p13_flangia (Autodesk Fusion 360 design; units mm, degrees)
Autodesk Fusion 360 part; units mm, degrees
sketch "Schizzo1" plane through (0, 0, 0) normal (0, 0, 1) x (1, 0, 0)
  line L0 (0, 0) -> (10000, 0)
  line L1 (10000, 0) -> (10000, 8000)
  line L2 (10000, 8000) -> (0, 8000)
  line L3 (0, 8000) -> (0, 0)
  line L4 (300, 300) -> (6000, 300)
  line L5 (6000, 300) -> (6000, 7700)
  line L6 (6000, 7700) -> (300, 7700)
  line L7 (300, 7700) -> (300, 300)
  line L8 (6100, 300) -> (9700, 300)
  line L9 (9700, 300) -> (9700, 4000)
  line L10 (9700, 4000) -> (6100, 4000)
  line L11 (6100, 4000) -> (6100, 300)
  line L12 (6100, 4100) -> (9700, 4100)
  line L13 (9700, 4100) -> (9700, 7700)
  line L14 (9700, 7700) -> (6100, 7700)
  line L15 (6100, 7700) -> (6100, 4100)
sketch "Schizzo2" plane through (0, 0, 0) normal (0, 0, 1) x (1, 0, 0)
  line L0 (2000, 0) -> (2900, 0)
  line L1 (2900, 0) -> (2900, 300)
  line L2 (2900, 300) -> (2000, 300)
  line L3 (2000, 300) -> (2000, 0)
  line L4 (6000, 1500) -> (6100, 1500)
  line L5 (6100, 1500) -> (6100, 2300)
  line L6 (6100, 2300) -> (6000, 2300)
  line L7 (6000, 2300) -> (6000, 1500)
  line L8 (6000, 5500) -> (6100, 5500)
  line L9 (6100, 5500) -> (6100, 6300)
  line L10 (6100, 6300) -> (6000, 6300)
  line L11 (6000, 6300) -> (6000, 5500)
sketch "Schizzo3" plane through (0, 0, 0) normal (0, 0, 1) x (1, 0, 0)
  line L0 (0, 3000) -> (300, 3000)
  line L1 (300, 3000) -> (300, 4500)
  line L2 (300, 4500) -> (0, 4500)
  line L3 (0, 4500) -> (0, 3000)
  line L4 (7400, 7700) -> (8600, 7700)
  line L5 (8600, 7700) -> (8600, 8000)
  line L6 (8600, 8000) -> (7400, 8000)
  line L7 (7400, 8000) -> (7400, 7700)
sketch "Schizzo4" plane through (0, 0, 0) normal (0, 0, 1) x (1, 0, 0)
  circle A0 centre (0, 0) radius 40
  circle A1 centre (0, 0) radius 15
extrude "Estrusione5" add sketch "Schizzo4" along normal blind 10
sketch "Schizzo5" plane through (0, 0, 10) normal (0, 0, 1) x (1, 0, 0)
  circle A0 centre (0, 0) radius 15
  circle A1 centre (0, 0) radius 40
  point P0 (30, 0)
  point P1 (0, 30)
  point P2 (-30, 0)
  point P3 (0, -30)
hole "Foratura1" at (30, 0, 10) direction (0, 0, -1) diameter 9 end through all
hole "Foratura2" at (0, 30, 10) direction (0, 0, -1) diameter 9 end through all
hole "Foratura3" at (-30, 0, 10) direction (0, 0, -1) diameter 9 end through all
hole "Foratura4" at (0, -30, 10) direction (0, 0, -1) diameter 9 end through all
equation "h_piano = 2700 mm" comment "altezza dei muri"
equation "sp_solaio = 200 mm" comment "solaio a terra"
equation "porta_h = 2100 mm" comment "altezza porte"
equation "fin_h = 1200 mm" comment "altezza finestre"
equation "davanzale = 900 mm" comment "altezza davanzale"
named bodies: "flangia"
